Autodesk Fusion 360 part; units mm, degrees
(part 5 of 11)
  spline S55 degree 5 poles (35.2404, 10.7239) (35.2549, 10.7283) (35.284, 10.7368) (35.3279, 10.7484) (35.3869, 10.7619) (35.4614, 10.7761) (35.5364, 10.7882) (35.6117, 10.7992) (35.6872, 10.8094) (35.7628, 10.8192) (35.8385, 10.8286) (35.9144, 10.8373) (35.9904, 10.8452) (36.0666, 10.8522) (36.1431, 10.8581) (36.2198, 10.8632) (36.2966, 10.8675) (36.3735, 10.8712) (36.4506, 10.8743) (36.5277, 10.8769) (36.605, 10.879) (36.6823, 10.8805) (36.7598, 10.8814) (36.8374, 10.8817) (36.9151, 10.8814) (36.9928, 10.8806) (37.0707, 10.8792) (37.1487, 10.8772) (37.2267, 10.8748) (37.3048, 10.8719) (37.383, 10.8685) (37.4612, 10.8646) (37.5396, 10.8603) (37.618, 10.8554) (37.6964, 10.8501) (37.7749, 10.8443) (37.8535, 10.838) (37.9322, 10.8313) (38.0109, 10.8242) (38.0896, 10.8166) (38.1684, 10.8086) (38.2473, 10.8001) (38.3262, 10.7912) (38.4051, 10.7819) (38.4841, 10.7721) (38.5631, 10.762) (38.6422, 10.7514) (38.7213, 10.7404) (38.8005, 10.729) (38.8796, 10.7172) (38.9589, 10.705) (39.0381, 10.6924) (39.1174, 10.6794) (39.1967, 10.666) (39.276, 10.6523) (39.3554, 10.6381) (39.4347, 10.6236) (39.5142, 10.6087) (39.5936, 10.5934) (39.673, 10.5777) (39.7525, 10.5617) (39.832, 10.5453) (39.9115, 10.5285) (39.991, 10.5113) (40.0705, 10.4938) (40.1501, 10.4759) (40.2296, 10.4577) (40.3092, 10.4391) (40.3887, 10.4202) (40.4683, 10.4009) (40.5479, 10.3812) (40.6116, 10.3652) (40.6593, 10.3531) (40.6912, 10.3449) (40.7071, 10.3408) knots 0 0 0 0 0 0 0.01428571 0.02857143 0.04285714 0.05714286 0.07142857 0.08571429 0.1 0.11428571 0.12857143 0.14285714 0.15714286 0.17142857 0.18571429 0.2 0.21428571 0.22857143 0.24285714 0.25714286 0.27142857 0.28571429 0.3 0.31428571 0.32857143 0.34285714 0.35714286 0.37142857 0.38571429 0.4 0.41428571 0.42857143 0.44285714 0.45714286 0.47142857 0.48571429 0.5 0.51428571 0.52857143 0.54285714 0.55714286 0.57142857 0.58571429 0.6 0.61428571 0.62857143 0.64285714 0.65714286 0.67142857 0.68571429 0.7 0.71428571 0.72857143 0.74285714 0.75714286 0.77142857 0.78571429 0.8 0.81428571 0.82857143 0.84285714 0.85714286 0.87142857 0.88571429 0.9 0.91428571 0.92857143 0.94285714 0.95714286 0.97142857 0.98571429 1 1 1 1 1 1
  line L55 (35.2404, 10.7239) -> (35.182, 10.7062)
  arc A110 (33.9431, 11.346) -> (35.182, 10.7062) centre (34.8915, 11.6631) ccw
  arc A111 (33.9431, 11.346) -> (33.6119, 12.2925) centre (0, 0) ccw
  line L56 (8, -8) -> (-8, -8)
  line L57 (-8, -8) -> (-8, 8)
  line L58 (-8, 8) -> (8, 8)
  line L59 (8, 8) -> (8, -8)
  dimension "d23" = 8
  dimension "d24" = 8
  dimension "d25" = 16
  dimension "d26" = 16
  constraint horizontal L56
  constraint vertical L57
  constraint horizontal L58
  constraint vertical L59
  measures "d23" distance of L56 A1.centre
  measures "d24" distance of L57 A1.centre
  measures "d25" distance of L57.end L58.end
  measures "d26" distance of L56.start L58.end
extrude "Extrude4" cut sketch "Sketch3 (3)" against normal blind 6 contours L56 L57 L58 L59 sketch seen with x (1, 0, 0) y (0, 1, 0) z (0, 0, 1) at (0, 0, 12) bodies 2 in component "Spur Gear (28 teeth)"
component "Spur Gear (10 teeth)" placed x (1, 0, 0) y (0, 1, 0) z (0, 0, 1) at (0, 0, 0)
component "Spur Gear (28 teeth)" placed x (1, 0, 0) y (0, 1, 0) z (0, 0, 1) at (0, 0, -12)

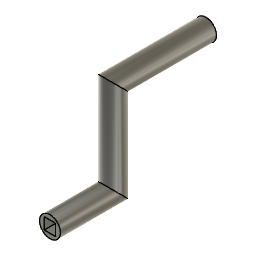
design "CRANK"
Autodesk Fusion 360 part; units mm, degrees
sketch "Sketch1" plane through (0, 0, 0) normal (0, 1, 0) x (1, 0, 0)
  circle A0 centre (0, 0) radius 31.369
  circle A1 centre (0, 0) radius 97.282
  dimension "d1" = 62.738
  dimension "d2" = 194.564
  constraint coincident A0.centre A1.centre
  measures "d1" diameter of A0
  measures "d2" diameter of A1
ref_plane "WorkPlane1" through (0, 2.921, 0) normal (0, 1, 0) x (1, 0, 0)
sketch "Sketch2" plane through (0, 2.921, 0) normal (0, 1, 0) x (1, 0, 0)
  circle A0 centre (0, 0) radius 31.369
  dimension "d15" = 62.738
  constraint coincident A0.centre origin
  measures "d15" diameter of A0
ref_plane "WorkPlane2" through (0, 59.563, 0) normal (0, 1, 0) x (1, 0, 0)
sketch "Sketch3" plane through (0, 59.563, 0) normal (0, 1, 0) x (1, 0, 0)
  circle A0 centre (0, 0) radius 31.369
  circle A1 centre (0, 0) radius 97.282
  dimension "d19" = 62.738
  dimension "d20" = 194.564
  constraint coincident A0.centre A1.centre
  measures "d19" diameter of A0
  measures "d20" diameter of A1
ref_plane "WorkPlane3" through (0, 2.921, 0) normal (0, 1, 0) x (1, 0, 0)
sketch "Sketch4" plane through (0, 2.921, 0) normal (0, 1, 0) x (1, 0, 0)
  circle A0 centre (0, 0) radius 92.456
  circle A1 centre (0, 0) radius 31.369
  dimension "d24" = 184.912
  dimension "d25" = 62.738
  constraint coincident A0.centre A1.centre
  measures "d24" diameter of A0
  measures "d25" diameter of A1
sketch "Sketch5" plane through (0, 0, 0) normal (0, 1, 0) x (1, 0, 0)
  circle A0 centre (0, 0) radius 30.861
  dimension "d28" = 61.722
  constraint coincident A0.centre origin
  measures "d28" diameter of A0
ref_plane "WorkPlane4" through (0, 76.2, 0) normal (0, 1, 0) x (1, 0, 0)
sketch "Sketch6" plane through (0, 76.2, 0) normal (0, 1, 0) x (1, 0, 0)
ref_plane "WorkPlane5" through (0, -19.05, 0) normal (0, -1, 0) x (-1, 0, 0)
sketch "Sketch7" plane through (0, -19.05, 0) normal (0, -1, 0) x (-1, 0, 0)
  circle A0 centre (0, 0) radius 25.4
  dimension "d33" = 50.8
  constraint coincident A0.centre origin
  measures "d33" diameter of A0
ref_plane "WorkPlane6" through (0, 62.23, 0) normal (0, 1, 0) x (1, 0, 0)
sketch "Sketch8" plane through (0, 62.23, 0) normal (0, 1, 0) x (1, 0, 0)
  circle A0 centre (0, 0) radius 31.425
  circle A1 centre (0, 0) radius 25.4019
  dimension "d38" = 62.85
  constraint coincident A0.centre A1.centre
  measures "d38" diameter of A0
ref_plane "WorkPlane7" through (0, 57.15, 0) normal (0, 1, 0) x (1, 0, 0)
sketch "Sketch9" plane through (0, 57.15, 0) normal (0, 1, 0) x (1, 0, 0)
  circle A0 centre (0, 0) radius 7.62
  dimension "d46" = 15.24
  constraint coincident A0.centre origin
  measures "d46" diameter of A0
ref_plane "WorkPlane8" through (0, 62.23, 0) normal (0, 1, 0) x (1, 0, 0)
sketch "Sketch10" plane through (0, 62.23, 0) normal (0, 1, 0) x (1, 0, 0)
  circle A0 centre (0, 0) radius 25.4
  circle A1 centre (0, 0) radius 44.45
  dimension "d50" = 50.8
  dimension "d51" = 88.9
  constraint coincident A0.centre A1.centre
  constraint concentric A0 A1
  measures "d50" diameter of A0
  measures "d51" diameter of A1
ref_plane "WorkPlane10" through (0, -19.05, 0) normal (0, -1, 0) x (-1, 0, 0)
sketch "Sketch12" plane through (0, -19.05, 0) normal (0, -1, 0) x (-1, 0, 0)
ref_plane "WorkPlane11" through (0, 86.36, 0) normal (0, 1, 0) x (1, 0, 0)
sketch "Sketch15" plane through (0, 86.36, 0) normal (0, 1, 0) x (1, 0, 0)
  line L0 (0, 0) -> (7.62, 0)
  line L1 (0, 0) -> (-7.62, 0)
  arc A0 (-7.62, 0) -> (7.62, 0) centre (0, 0) ccw
  dimension "d76" = 15.24
  constraint coincident L0.start L1.start
  constraint horizontal L0
  constraint parallel L0 L1
  measures "d76" diameter of A0
sketch "Sketch17" plane through (0, 86.36, 0) normal (0, 1, 0) x (1, 0, 0)
  circle A0 centre (0, 0) radius 9
  line L0 (7.8616, -0.2306) -> (-7.8616, -0.2306)
  arc A1 (7.8616, -0.2306) -> (-7.8616, -0.2306) centre (0, 0) ccw
  dimension "d80" = 18
  dimension "d81" = 15.73
  constraint coincident A0.centre A1.centre
  measures "d80" diameter of A0
  measures "d81" diameter of A1
ref_plane "WorkPlane12" through (0, 127.18, 0) normal (0, 1, 0) x (1, 0, 0)
sketch "Sketch18" plane through (0, 127.18, 0) normal (0, 1, 0) x (1, 0, 0)
  circle A0 centre (0, 0) radius 9
  dimension "d85" = 18
  constraint coincident A0.centre origin
  measures "d85" diameter of A0
ref_plane "WorkPlane14" through (9, 117.0493, 0) normal (1, 0, 0) x (0, 0, 1)
ref_plane "WorkPlane15" through (0, 117.0493, 0) normal (1, 0, 0) x (0, 0, 1)
sketch "Sketch19" plane through (0, 0, 0) normal (1, 0, 0) x (0, 1, 0)
  line L0 (127, 0) -> (141, 0)
  line L1 (141, 0) -> (141, 80)
  line L2 (141, 80) -> (221, 80)
  dimension "d89" = 80
  dimension "d90" = 80
  constraint horizontal L0
  constraint perpendicular L0 L1
  constraint perpendicular L1 L2
  measures "d89" distance of L0.end L1.end
  measures "d90" distance of L1.end L2.end
sweep "Sweep1" add profiles "Sketch18" path "Sketch19" along L0 L1 L2 section 1
ref_plane "WorkPlane16" through (0, -19.05, 0) normal (0, -1, 0) x (-1, 0, 0)
sketch "Sketch20" plane through (0, -19.05, 0) normal (0, -1, 0) x (-1, 0, 0)
  circle A0 centre (0, 0) radius 30
  dimension "d98" = 60
  constraint coincident A0.centre origin
  measures "d98" diameter of A0
ref_plane "WorkPlane17" through (0, -31.05, 0) normal (0, -1, 0) x (-1, 0, 0)
sketch "Sketch21" plane through (0, -31.05, 0) normal (0, -1, 0) x (-1, 0, 0)
ref_plane "WorkPlane18" through (0, 127, 0) normal (0, -1, 0) x (-1, 0, 0)
sketch "Sketch22" plane through (0, 127, 0) normal (0, -1, 0) x (-1, 0, 0)
  circle A0 centre (0, 0) radius 9
  line L0 (0, 0) -> (-7.6177, 0)
  line L1 (0, 0) -> (7.6177, 0)
  arc A1 (7.6177, 0) -> (-7.6177, 0) centre (0, 0) ccw
  dimension "d115" = 18
  constraint coincident A0.centre L0.start
  constraint concentric A0 A1
  constraint horizontal L0
  constraint parallel L0 L1
  measures "d115" diameter of A0
extrude "Extrude14" add sketch "Sketch22" along normal blind 40.5 contours A0 | L0 L1 A1
ref_plane "WorkPlane20" through (0, 86.5, 0) normal (0, -1, 0) x (-1, 0, 0)
sketch "Sketch24" plane through (0, 86.5, 0) normal (0, -1, 0) x (-1, 0, 0)
  line L0 (5, 5) -> (-5, 5)
  line L1 (-5, 5) -> (-5, -5)
  line L2 (-5, -5) -> (5, -5)
  line L3 (5, -5) -> (5, 5)
  line L4 (5, 5) -> (-5, -5) construction
  line L5 (-5, 5) -> (5, -5) construction
  dimension "d125" = 10
  dimension "d126" = 10
  constraint horizontal L0
  constraint perpendicular L0 L1
  constraint parallel L0 L2
  constraint parallel L1 L3
  constraint coincident L4 origin
  constraint coincident L5 origin
  measures "d125" distance of L1.end L2.end
  measures "d126" distance of L0.end L1.end
extrude "Extrude16" cut sketch "Sketch24" against normal blind 40

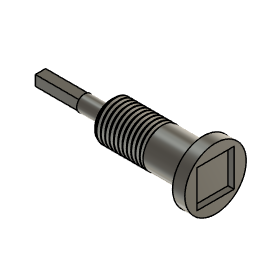
design "Green Part (Chamfered)"
Autodesk Fusion 360 part; units mm, degrees
sketch "Sketch1" plane through (0, 0, 0) normal (1, 0, 0) x (0, 1, 0)
  circle A0 centre (0, 0) radius 20
  dimension "d1" = 40
  constraint coincident A0.centre origin
  measures "d1" diameter of A0
extrude "Extrude1" add sketch "Sketch1" along normal blind 95
thread "Thread1" "ANSI Unified Screw Threads 1.5 1 1/2-6 UNC 3A" major diameter 37.8689 minor diameter 33.0606 pitch 4.2333 angle 60 modelled right hand crest width 0.6179 on face at (63.3333, 19.9751, -0.9969) from (0, 0, 0) to (55, 0, 0) crest through (-1.0583, 18.9344, 0)
sketch "Sketch2" plane through (0, 0, 0) normal (0, 1, 0) x (1, 0, 0)
  line L0 (0, 0) -> (0, -19)
  line L1 (0, -19) -> (8, -19)
  line L2 (8, -19) -> (5, -16)
  line L3 (5, -16) -> (5, 0)
  line L4 (5, 0) -> (0, 0)
  dimension "d6" = 19
  dimension "d7" = 5
  dimension "d8" = 45
  dimension "d9" = 3
  constraint coincident L0.start L4.end
  constraint vertical L0
  constraint perpendicular L0 L1
  constraint perpendicular L1 L3
  constraint perpendicular L0 L4
  measures "d6" distance of L0.start L0.end
  measures "d7" distance of L0 L3
  measures "d8" angle of L1 L2
  measures "d9" horizontal distance of L1.end L2.end
revolve "Revolve1" cut sketch "Sketch2" angle 360 about axis through (0, 0, 0) along (1, 0, 0)
sketch "Sketch3" plane through (5, 0, 0) normal (-1, 0, 0) x (0, -1, 0)
  circle A0 centre (0, 0) radius 16
  circle A1 centre (0, 0) radius 7.62
  dimension "d11" = 15.24
  constraint coincident A0.centre A1.centre
  measures "d11" diameter of A1
extrude "Extrude2" add sketch "Sketch3" along normal blind 26.2 contours A1
sketch "Sketch4" plane through (-21.2, 0, 0) normal (-1, 0, 0) x (0, -1, 0)
  circle A0 centre (0, 0) radius 7.62
  line L0 (5, -5) -> (-5, -5)
  line L1 (-5, -5) -> (-5, 5)
  line L2 (-5, 5) -> (5, 5)
  line L3 (5, 5) -> (5, -5)
  line L4 (5, -5) -> (-5, 5) construction
  line L5 (-5, -5) -> (5, 5) construction
  dimension "d14" = 10
  dimension "d15" = 10
  constraint horizontal L0
  constraint perpendicular L0 L1
  constraint parallel L0 L2
  constraint parallel L1 L3
  constraint coincident L4 A0.centre
  constraint coincident L5 A0.centre
  constraint coincident A0.centre origin
  measures "d14" distance of L1.end L2.end
  measures "d15" distance of L0.end L1.end
extrude "Extrude3" add sketch "Sketch4" along normal blind 43 contours L0 L1 L2 L3
sketch "Sketch5" plane through (95, 0, 0) normal (1, 0, 0) x (0, 1, 0)
  circle A0 centre (0, 0) radius 18.9344
  circle A1 centre (0, 0) radius 30
  dimension "d18" = 60
  constraint concentric A0 A1
  measures "d18" diameter of A1
extrude "Extrude4" add sketch "Sketch5" along normal blind 12 contours A0 | A1
sketch "Sketch6" plane through (107, 0, 0) normal (1, 0, 0) x (0, 1, 0)
  circle A0 centre (0, 0) radius 30
  line L0 (18.2, -18.2) -> (-18.2, -18.2)
  line L1 (-18.2, -18.2) -> (-18.2, 18.2)
  line L2 (-18.2, 18.2) -> (18.2, 18.2)
  line L3 (18.2, 18.2) -> (18.2, -18.2)
  line L4 (18.2, -18.2) -> (-18.2, 18.2) construction
  line L5 (-18.2, -18.2) -> (18.2, 18.2) construction
  dimension "d21" = 36.4
  dimension "d22" = 36.4
  constraint horizontal L0
  constraint perpendicular L0 L1
  constraint parallel L0 L2
  constraint parallel L1 L3
  constraint coincident L4 A0.centre
  constraint coincident L5 A0.centre
  constraint coincident A0.centre origin
  measures "d21" distance of L1.end L2.end
  measures "d22" distance of L0.start L2.end
extrude "Extrude5" cut sketch "Sketch6" against normal blind 6 contours L0 L1 L2 L3

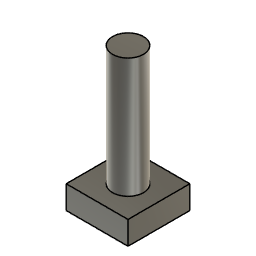
design "Blue Shaft"
Autodesk Fusion 360 part; units mm, degrees
sketch "Sketch1" plane through (0, 0, 0) normal (0, 0, 1) x (1, 0, 0)
  line L0 (-25, 25) -> (-9, 25)
  line L1 (-9, 25) -> (-9, 9)
  line L2 (-9, 9) -> (-25, 9)
  line L3 (-25, 9) -> (-25, 25)
  dimension "d1" = 16
  dimension "d2" = 16
  constraint horizontal L0
  constraint vertical L1
  constraint horizontal L2
  constraint vertical L3
  measures "d1" distance of L0.start L0.end
  measures "d2" distance of L0.end L1.end
extrude "Extrude1" add sketch "Sketch1" along normal blind 6
move_body "Move1" bodies 1 to x (1, 0, 0) y (0, 1, 0) z (0, 0, 1) at (18.0169, -15.1205, 0)
move_body "Move2" bodies 1 to x (1, 0, 0) y (0, 1, 0) z (0, 0, 1) at (-5.5215, -1.8795, -5.7458)
move_body "Move3" bodies 1 to x (1, 0, 0) y (0, 1, 0) z (0, 0, 1) at (-0.1134, -7.519, 0)
move_body "Move4" bodies 1 to x (1, 0, 0) y (0, 1, 0) z (0, 0, 1) at (4.618, 7.519, -0.2542)
sketch "Sketch2" plane through (0, 0, 0) normal (0, 0, 1) x (-1, 0, 0)
  line L0 (8, 8) -> (-8, 8)
  line L1 (-8, 8) -> (-8, -8)
  line L2 (-8, -8) -> (8, -8)
  line L3 (8, -8) -> (8, 8)
  circle A0 centre (0, 0) radius 4
  dimension "d5" = 8
  constraint coincident A0.centre origin
  measures "d5" diameter of A0
extrude "Extrude2" add sketch "Sketch2" along normal blind 31 contours A0

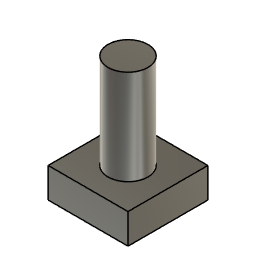
design "Black Shaft"
Autodesk Fusion 360 part; units mm, degrees
sketch "Sketch1" plane through (0, 0, 0) normal (0, 0, 1) x (1, 0, 0)
  line L0 (-8, 8) -> (8, 8)
  line L1 (8, 8) -> (8, -8)
  line L2 (8, -8) -> (-8, -8)
  line L3 (-8, -8) -> (-8, 8)
  dimension "d1" = 8
  dimension "d2" = 8
  dimension "d3" = 16
  dimension "d4" = 16
  constraint horizontal L0
  constraint vertical L1
  constraint horizontal L2
  constraint vertical L3
  measures "d1" distance of origin L1
  measures "d2" distance of origin L0
  measures "d3" distance of L1.end L2.end
  measures "d4" distance of L0.start L2.end
extrude "Extrude1" add sketch "Sketch1" along normal blind 6
sketch "Sketch2" plane through (0, 0, 6) normal (0, 0, 1) x (-1, 0, 0)
  line L0 (8, 8) -> (-8, 8)
  line L1 (-8, 8) -> (-8, -8)
  line L2 (-8, -8) -> (8, -8)
  line L3 (8, -8) -> (8, 8)
  circle A0 centre (0, 0) radius 4
  dimension "d7" = 8
  constraint coincident A0.centre origin
  measures "d7" diameter of A0
extrude "Extrude2" add sketch "Sketch2" along normal blind 19 contours A0

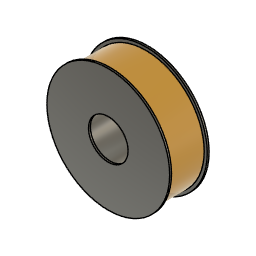
design "Spool"
Autodesk Fusion 360 part; units mm, degrees
sketch "Sketch1" plane through (0, 0, 0) normal (0, 1, 0) x (1, 0, 0)
  circle A0 centre (0, 0) radius 31.369
  circle A1 centre (0, 0) radius 97.282
  dimension "d1" = 62.738
  dimension "d2" = 194.564
  constraint coincident A0.centre A1.centre
  measures "d1" diameter of A0
  measures "d2" diameter of A1
extrude "Extrude1" add sketch "Sketch1" along normal blind 2.921 makes body 1
ref_plane "WorkPlane1" through (0, 2.921, 0) normal (0, 1, 0) x (1, 0, 0)
sketch "Sketch2" plane through (0, 2.921, 0) normal (0, 1, 0) x (1, 0, 0)
  circle A0 centre (0, 0) radius 31.369
  dimension "d15" = 62.738
  constraint coincident A0.centre origin
  measures "d15" diameter of A0
ref_plane "WorkPlane2" through (0, 59.563, 0) normal (0, 1, 0) x (1, 0, 0)
sketch "Sketch3" plane through (0, 59.563, 0) normal (0, 1, 0) x (1, 0, 0)
  circle A0 centre (0, 0) radius 31.369
  circle A1 centre (0, 0) radius 97.282
  dimension "d19" = 62.738
  dimension "d20" = 194.564
  constraint coincident A0.centre A1.centre
  measures "d19" diameter of A0
  measures "d20" diameter of A1
extrude "Extrude3" add sketch "Sketch3" along normal blind 2.921 separate body makes body 2
ref_plane "WorkPlane3" through (0, 2.921, 0) normal (0, 1, 0) x (1, 0, 0)
sketch "Sketch4" plane through (0, 2.921, 0) normal (0, 1, 0) x (1, 0, 0)
  circle A0 centre (0, 0) radius 92.456
  circle A1 centre (0, 0) radius 31.369
  dimension "d24" = 184.912
  dimension "d25" = 62.738
  constraint coincident A0.centre A1.centre
  measures "d24" diameter of A0
  measures "d25" diameter of A1
extrude "Extrude4" add sketch "Sketch4" along normal blind 56.642 separate body makes body 3
sketch "Sketch5" plane through (0, 0, 0) normal (0, 1, 0) x (1, 0, 0)
  circle A0 centre (0, 0) radius 30.861
  dimension "d28" = 61.722
  constraint coincident A0.centre origin
  measures "d28" diameter of A0
ref_plane "WorkPlane4" through (0, 76.2, 0) normal (0, 1, 0) x (1, 0, 0)
sketch "Sketch6" plane through (0, 76.2, 0) normal (0, 1, 0) x (1, 0, 0)
ref_plane "WorkPlane5" through (0, -19.05, 0) normal (0, -1, 0) x (-1, 0, 0)
sketch "Sketch7" plane through (0, -19.05, 0) normal (0, -1, 0) x (-1, 0, 0)
  circle A0 centre (0, 0) radius 25.4
  dimension "d33" = 50.8
  constraint coincident A0.centre origin
  measures "d33" diameter of A0
ref_plane "WorkPlane6" through (0, 62.23, 0) normal (0, 1, 0) x (1, 0, 0)
sketch "Sketch8" plane through (0, 62.23, 0) normal (0, 1, 0) x (1, 0, 0)
  circle A0 centre (0, 0) radius 31.425
  circle A1 centre (0, 0) radius 25.4019
  dimension "d38" = 62.85
  constraint coincident A0.centre A1.centre
  measures "d38" diameter of A0
ref_plane "WorkPlane7" through (0, 57.15, 0) normal (0, 1, 0) x (1, 0, 0)
sketch "Sketch9" plane through (0, 57.15, 0) normal (0, 1, 0) x (1, 0, 0)
  circle A0 centre (0, 0) radius 7.62
  dimension "d46" = 15.24
  constraint coincident A0.centre origin
  measures "d46" diameter of A0
ref_plane "WorkPlane8" through (0, 62.23, 0) normal (0, 1, 0) x (1, 0, 0)
sketch "Sketch10" plane through (0, 62.23, 0) normal (0, 1, 0) x (1, 0, 0)
  circle A0 centre (0, 0) radius 25.4
  circle A1 centre (0, 0) radius 44.45
  dimension "d50" = 50.8
  dimension "d51" = 88.9
  constraint coincident A0.centre A1.centre
  constraint concentric A0 A1
  measures "d50" diameter of A0
  measures "d51" diameter of A1
ref_plane "WorkPlane10" through (0, -19.05, 0) normal (0, -1, 0) x (-1, 0, 0)
sketch "Sketch12" plane through (0, -19.05, 0) normal (0, -1, 0) x (-1, 0, 0)
ref_plane "WorkPlane11" through (0, 86.36, 0) normal (0, 1, 0) x (1, 0, 0)
sketch "Sketch15" plane through (0, 86.36, 0) normal (0, 1, 0) x (1, 0, 0)
  line L0 (0, 0) -> (7.62, 0)
  line L1 (0, 0) -> (-7.62, 0)
  arc A0 (-7.62, 0) -> (7.62, 0) centre (0, 0) ccw
  dimension "d76" = 15.24
  constraint coincident L0.start L1.start
  constraint horizontal L0
  constraint parallel L0 L1
  measures "d76" diameter of A0
sketch "Sketch17" plane through (0, 86.36, 0) normal (0, 1, 0) x (1, 0, 0)
  circle A0 centre (0, 0) radius 9
  line L0 (7.8616, -0.2306) -> (-7.8616, -0.2306)
  arc A1 (7.8616, -0.2306) -> (-7.8616, -0.2306) centre (0, 0) ccw
  dimension "d80" = 18
  dimension "d81" = 15.73
  constraint coincident A0.centre A1.centre
  measures "d80" diameter of A0
  measures "d81" diameter of A1
ref_plane "WorkPlane12" through (0, 127.18, 0) normal (0, 1, 0) x (1, 0, 0)
sketch "Sketch18" plane through (0, 127.18, 0) normal (0, 1, 0) x (1, 0, 0)
  circle A0 centre (0, 0) radius 9
  dimension "d85" = 18
  constraint coincident A0.centre origin
  measures "d85" diameter of A0
ref_plane "WorkPlane14" through (9, 117.0493, 0) normal (1, 0, 0) x (0, 0, 1)
ref_plane "WorkPlane15" through (0, 117.0493, 0) normal (1, 0, 0) x (0, 0, 1)
sketch "Sketch19" plane through (0, 0, 0) normal (1, 0, 0) x (0, 1, 0)
  line L0 (127, 0) -> (141, 0)
  line L1 (141, 0) -> (141, 80)
  line L2 (141, 80) -> (221, 80)
  dimension "d89" = 80
  dimension "d90" = 80
  constraint horizontal L0
  constraint perpendicular L0 L1
  constraint perpendicular L1 L2
  measures "d89" distance of L0.end L1.end
  measures "d90" distance of L1.end L2.end
ref_plane "WorkPlane16" through (0, -19.05, 0) normal (0, -1, 0) x (-1, 0, 0)
sketch "Sketch20" plane through (0, -19.05, 0) normal (0, -1, 0) x (-1, 0, 0)
  circle A0 centre (0, 0) radius 30
  dimension "d98" = 60
  constraint coincident A0.centre origin
  measures "d98" diameter of A0
ref_plane "WorkPlane17" through (0, -31.05, 0) normal (0, -1, 0) x (-1, 0, 0)
sketch "Sketch21" plane through (0, -31.05, 0) normal (0, -1, 0) x (-1, 0, 0)
ref_plane "WorkPlane18" through (0, 127, 0) normal (0, -1, 0) x (-1, 0, 0)
sketch "Sketch22" plane through (0, 127, 0) normal (0, -1, 0) x (-1, 0, 0)
  circle A0 centre (0, 0) radius 9
  line L0 (0, 0) -> (-7.6177, 0)
  line L1 (0, 0) -> (7.6177, 0)
  arc A1 (7.6177, 0) -> (-7.6177, 0) centre (0, 0) ccw
  dimension "d115" = 18
  constraint coincident A0.centre L0.start
  constraint concentric A0 A1
  constraint horizontal L0
  constraint parallel L0 L1
  measures "d115" diameter of A0

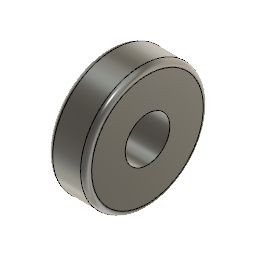
design "608RS Bearing"
Autodesk Fusion 360 part; units mm, degrees
sketch "Sketch1" plane through (0, 0, 0) normal (1, 0, 0) x (0, 1, 0)
  circle A0 centre (0, 0) radius 11
  circle A1 centre (0, 0) radius 4
  dimension "d1" = 22
  dimension "d2" = 8
  constraint coincident A0.centre A1.centre
  constraint concentric A0 A1
  measures "d1" diameter of A0
  measures "d2" diameter of A1
extrude "Extrude1" add sketch "Sketch1" along normal blind 7
fillet "Fillet1" radius 1 2 edges at (0, -10.2556, -3.9778) (7, -10.2556, -3.9778)

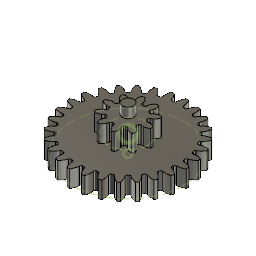
design "Blue Gear (new)"
description: Spur Gear; Module: 2.800000; Num Teeth: 28; Pressure Angle: 20.000000; Backlash: 0.00 mm
description: Spur Gear; Module: 2.800000; Num Teeth: 10; Pressure Angle: 20.000000; Backlash: 0.00 mm
Autodesk Fusion 360 part; units mm, degrees
sketch "Sketch1" plane through (0, 0, 0) normal (0, 0, 1) x (1, 0, 0) in component "Spur Gear (28 teeth)"
  circle A0 centre (0, 0) radius 35.7892
extrude "Extrude1" add sketch "Sketch1" along normal blind 12 makes body 1 in component "Spur Gear (28 teeth)"
sketch "Sketch2" plane through (0, 0, 0) normal (0, 0, 1) x (1, 0, 0) in component "Spur Gear (28 teeth)"
  spline S0 degree 5 poles (36.7431, -2.6133) (36.7583, -2.6144) (36.7885, -2.6161) (36.8339, -2.6177) (36.8945, -2.6178) (36.9702, -2.615) (37.0461, -2.6101) (37.1219, -2.6041) (37.1978, -2.5973) (37.2736, -2.59) (37.3495, -2.5823) (37.4254, -2.5739) (37.5013, -2.5647) (37.5772, -2.5545) (37.6531, -2.5433) (37.7289, -2.5312) (37.8048, -2.5183) (37.8806, -2.5048) (37.9564, -2.4907) (38.0322, -2.476) (38.108, -2.4608) (38.1838, -2.4451) (38.2595, -2.4287) (38.3352, -2.4118) (38.4109, -2.3942) (38.4865, -2.3761) (38.5621, -2.3574) (38.6377, -2.3382) (38.7132, -2.3184) (38.7887, -2.2982) (38.8642, -2.2775) (38.9396, -2.2563) (39.015, -2.2346) (39.0904, -2.2125) (39.1657, -2.1898) (39.2409, -2.1667) (39.3162, -2.1431) (39.3913, -2.1191) (39.4665, -2.0946) (39.5415, -2.0697) (39.6166, -2.0443) (39.6916, -2.0185) (39.7665, -1.9923) (39.8414, -1.9656) (39.9162, -1.9385) (39.991, -1.911) (40.0658, -1.8831) (40.1405, -1.8548) (40.2151, -1.8261) (40.2896, -1.797) (40.3642, -1.7675) (40.4386, -1.7375) (40.513, -1.7072) (40.5874, -1.6765) (40.6616, -1.6455) (40.7359, -1.614) (40.81, -1.5822) (40.8841, -1.55) (40.9581, -1.5174) (41.0321, -1.4844) (41.106, -1.4511) (41.1798, -1.4174) (41.2536, -1.3834) (41.3273, -1.349) (41.401, -1.3142) (41.4745, -1.2791) (41.548, -1.2436) (41.6215, -1.2078) (41.6948, -1.1716) (41.7681, -1.1351) (41.8413, -1.0982) (41.8998, -1.0684) (41.9437, -1.0459) (41.9729, -1.0309) (41.9875, -1.0233) knots 0 0 0 0 0 0 0.01428571 0.02857143 0.04285714 0.05714286 0.07142857 0.08571429 0.1 0.11428571 0.12857143 0.14285714 0.15714286 0.17142857 0.18571429 0.2 0.21428571 0.22857143 0.24285714 0.25714286 0.27142857 0.28571429 0.3 0.31428571 0.32857143 0.34285714 0.35714286 0.37142857 0.38571429 0.4 0.41428571 0.42857143 0.44285714 0.45714286 0.47142857 0.48571429 0.5 0.51428571 0.52857143 0.54285714 0.55714286 0.57142857 0.58571429 0.6 0.61428571 0.62857143 0.64285714 0.65714286 0.67142857 0.68571429 0.7 0.71428571 0.72857143 0.74285714 0.75714286 0.77142857 0.78571429 0.8 0.81428571 0.82857143 0.84285714 0.85714286 0.87142857 0.88571429 0.9 0.91428571 0.92857143 0.94285714 0.95714286 0.97142857 0.98571429 1 1 1 1 1 1
  spline S1 degree 5 poles (36.7431, 2.6133) (36.7583, 2.6144) (36.7885, 2.6161) (36.8339, 2.6177) (36.8945, 2.6178) (36.9702, 2.615) (37.0461, 2.6101) (37.1219, 2.6041) (37.1978, 2.5973) (37.2736, 2.59) (37.3495, 2.5823) (37.4254, 2.5739) (37.5013, 2.5647) (37.5772, 2.5545) (37.6531, 2.5433) (37.7289, 2.5312) (37.8048, 2.5183) (37.8806, 2.5048) (37.9564, 2.4907) (38.0322, 2.476) (38.108, 2.4608) (38.1838, 2.4451) (38.2595, 2.4287) (38.3352, 2.4118) (38.4109, 2.3942) (38.4865, 2.3761) (38.5621, 2.3574) (38.6377, 2.3382) (38.7132, 2.3184) (38.7887, 2.2982) (38.8642, 2.2775) (38.9396, 2.2563) (39.015, 2.2346) (39.0904, 2.2125) (39.1657, 2.1898) (39.2409, 2.1667) (39.3162, 2.1431) (39.3913, 2.1191) (39.4665, 2.0946) (39.5415, 2.0697) (39.6166, 2.0443) (39.6916, 2.0185) (39.7665, 1.9923) (39.8414, 1.9656) (39.9162, 1.9385) (39.991, 1.911) (40.0658, 1.8831) (40.1405, 1.8548) (40.2151, 1.8261) (40.2896, 1.797) (40.3642, 1.7675) (40.4386, 1.7375) (40.513, 1.7072) (40.5874, 1.6765) (40.6616, 1.6455) (40.7359, 1.614) (40.81, 1.5822) (40.8841, 1.55) (40.9581, 1.5174) (41.0321, 1.4844) (41.106, 1.4511) (41.1798, 1.4174) (41.2536, 1.3834) (41.3273, 1.349) (41.401, 1.3142) (41.4745, 1.2791) (41.548, 1.2436) (41.6215, 1.2078) (41.6948, 1.1716) (41.7681, 1.1351) (41.8413, 1.0982) (41.8998, 1.0684) (41.9437, 1.0459) (41.9729, 1.0309) (41.9875, 1.0233) knots 0 0 0 0 0 0 0.01428571 0.02857143 0.04285714 0.05714286 0.07142857 0.08571429 0.1 0.11428571 0.12857143 0.14285714 0.15714286 0.17142857 0.18571429 0.2 0.21428571 0.22857143 0.24285714 0.25714286 0.27142857 0.28571429 0.3 0.31428571 0.32857143 0.34285714 0.35714286 0.37142857 0.38571429 0.4 0.41428571 0.42857143 0.44285714 0.45714286 0.47142857 0.48571429 0.5 0.51428571 0.52857143 0.54285714 0.55714286 0.57142857 0.58571429 0.6 0.61428571 0.62857143 0.64285714 0.65714286 0.67142857 0.68571429 0.7 0.71428571 0.72857143 0.74285714 0.75714286 0.77142857 0.78571429 0.8 0.81428571 0.82857143 0.84285714 0.85714286 0.87142857 0.88571429 0.9 0.91428571 0.92857143 0.94285714 0.95714286 0.97142857 0.98571429 1 1 1 1 1 1
  arc A0 (41.9875, -1.0233) -> (41.9875, 1.0233) centre (0, 0) ccw
  line L0 (35.689, -2.5391) -> (36.7431, -2.6133)
  line L1 (35.689, 2.5391) -> (36.7431, 2.6133)
  line L2 (35.689, -2.5391) -> (35.689, 2.5391)
  point P0 (37.1135, -2.6046)
  point P1 (37.4859, -2.5664)
  point P2 (37.8595, -2.5085)
  point P3 (38.234, -2.4342)
  point P4 (38.6091, -2.3454)
  point P5 (38.9846, -2.2433)
  point P6 (39.3604, -2.1289)
  point P7 (39.7364, -2.0027)
  point P8 (40.1123, -1.8654)
  point P9 (40.4882, -1.7173)
  point P10 (40.8637, -1.5588)
  point P11 (41.2389, -1.3901)
  point P12 (41.6135, -1.2116)
  point P13 (37.1135, 2.6046)
  point P14 (37.4859, 2.5664)
  point P15 (37.8595, 2.5085)
  point P16 (38.234, 2.4342)
  point P17 (38.6091, 2.3454)
  point P18 (38.9846, 2.2433)
  point P19 (39.3604, 2.1289)
  point P20 (39.7364, 2.0027)
  point P21 (40.1123, 1.8654)
  point P22 (40.4882, 1.7173)
  point P23 (40.8637, 1.5588)
  point P24 (41.2389, 1.3901)
  point P25 (41.6135, 1.2116)
extrude "Extrude2" add sketch "Sketch2" along normal blind 12 bodies 1 in component "Spur Gear (28 teeth)"
fillet "Fillet1" radius 1 2 edges at (35.699, -2.5397, 6) (35.699, 2.5397, 6) on bodies 1 in component "Spur Gear (28 teeth)"
pattern_circular "C-Pattern1" count 28 over 360 about axis through (0, 0, 0) along (0, 0, 1) of "Extrude2", "Fillet1" in component "Spur Gear (28 teeth)"
sketch "Sketch3" plane through (0, 0, 0) normal (0, 0, 1) x (1, 0, 0) in component "Spur Gear (28 teeth)"
  circle A0 centre (0, 0) radius 39.2 construction
sketch "Sketch1 (2)" plane through (0, 0, 0) normal (0, 0, 1) x (1, 0, 0) in component "Spur Gear (10 teeth)"
  circle A0 centre (0, 0) radius 10.5892
extrude "Extrude1'" add sketch "Sketch1 (2)" along normal blind 12 separate body makes body 2 in component "Spur Gear (10 teeth)"
sketch "Sketch2 (2)" plane through (0, 0, 0) normal (0, 0, 1) x (1, 0, 0) in component "Spur Gear (10 teeth)"
  spline S0 degree 5 poles (12.9616, -2.2514) (12.9724, -2.2533) (12.9939, -2.2566) (13.0264, -2.2606) (13.0698, -2.2637) (13.1245, -2.2647) (13.1793, -2.2636) (13.2343, -2.2613) (13.2894, -2.2583) (13.3446, -2.2548) (13.3998, -2.2507) (13.4551, -2.246) (13.5104, -2.2404) (13.5658, -2.2337) (13.6212, -2.226) (13.6767, -2.2173) (13.7323, -2.2079) (13.7878, -2.1977) (13.8434, -2.187) (13.899, -2.1756) (13.9546, -2.1637) (14.0101, -2.1511) (14.0657, -2.138) (14.1213, -2.1241) (14.1769, -2.1096) (14.2325, -2.0944) (14.2881, -2.0787) (14.3436, -2.0624) (14.3991, -2.0455) (14.4546, -2.0281) (14.5101, -2.0101) (14.5655, -1.9917) (14.6209, -1.9726) (14.6763, -1.953) (14.7316, -1.9329) (14.7869, -1.9123) (14.8421, -1.8911) (14.8973, -1.8695) (14.9524, -1.8473) (15.0075, -1.8247) (15.0626, -1.8015) (15.1175, -1.7779) (15.1724, -1.7538) (15.2273, -1.7292) (15.282, -1.7041) (15.3368, -1.6785) (15.3914, -1.6525) (15.446, -1.626) (15.5004, -1.5991) (15.5548, -1.5717) (15.6092, -1.5439) (15.6634, -1.5156) (15.7176, -1.4868) (15.7717, -1.4576) (15.8256, -1.428) (15.8795, -1.3979) (15.9333, -1.3674) (15.9871, -1.3365) (16.0407, -1.3051) (16.0942, -1.2733) (16.1476, -1.2411) (16.2009, -1.2085) (16.2541, -1.1755) (16.3072, -1.142) (16.3602, -1.1081) (16.413, -1.0738) (16.4658, -1.0391) (16.5184, -1.004) (16.571, -0.9685) (16.6234, -0.9327) (16.6757, -0.8964) (16.7174, -0.867) (16.7486, -0.8448) (16.7695, -0.8299) (16.7799, -0.8225) knots 0 0 0 0 0 0 0.01428571 0.02857143 0.04285714 0.05714286 0.07142857 0.08571429 0.1 0.11428571 0.12857143 0.14285714 0.15714286 0.17142857 0.18571429 0.2 0.21428571 0.22857143 0.24285714 0.25714286 0.27142857 0.28571429 0.3 0.31428571 0.32857143 0.34285714 0.35714286 0.37142857 0.38571429 0.4 0.41428571 0.42857143 0.44285714 0.45714286 0.47142857 0.48571429 0.5 0.51428571 0.52857143 0.54285714 0.55714286 0.57142857 0.58571429 0.6 0.61428571 0.62857143 0.64285714 0.65714286 0.67142857 0.68571429 0.7 0.71428571 0.72857143 0.74285714 0.75714286 0.77142857 0.78571429 0.8 0.81428571 0.82857143 0.84285714 0.85714286 0.87142857 0.88571429 0.9 0.91428571 0.92857143 0.94285714 0.95714286 0.97142857 0.98571429 1 1 1 1 1 1
  spline S1 degree 5 poles (12.9616, 2.2514) (12.9724, 2.2533) (12.9939, 2.2566) (13.0264, 2.2606) (13.0698, 2.2637) (13.1245, 2.2647) (13.1793, 2.2636) (13.2343, 2.2613) (13.2894, 2.2583) (13.3446, 2.2548) (13.3998, 2.2507) (13.4551, 2.246) (13.5104, 2.2404) (13.5658, 2.2337) (13.6212, 2.226) (13.6767, 2.2173) (13.7323, 2.2079) (13.7878, 2.1977) (13.8434, 2.187) (13.899, 2.1756) (13.9546, 2.1637) (14.0101, 2.1511) (14.0657, 2.138) (14.1213, 2.1241) (14.1769, 2.1096) (14.2325, 2.0944) (14.2881, 2.0787) (14.3436, 2.0624) (14.3991, 2.0455) (14.4546, 2.0281) (14.5101, 2.0101) (14.5655, 1.9917) (14.6209, 1.9726) (14.6763, 1.953) (14.7316, 1.9329) (14.7869, 1.9123) (14.8421, 1.8911) (14.8973, 1.8695) (14.9524, 1.8473) (15.0075, 1.8247) (15.0626, 1.8015) (15.1175, 1.7779) (15.1724, 1.7538) (15.2273, 1.7292) (15.282, 1.7041) (15.3368, 1.6785) (15.3914, 1.6525) (15.446, 1.626) (15.5004, 1.5991) (15.5548, 1.5717) (15.6092, 1.5439) (15.6634, 1.5156) (15.7176, 1.4868) (15.7717, 1.4576) (15.8256, 1.428) (15.8795, 1.3979) (15.9333, 1.3674) (15.9871, 1.3365) (16.0407, 1.3051) (16.0942, 1.2733) (16.1476, 1.2411) (16.2009, 1.2085) (16.2541, 1.1755) (16.3072, 1.142) (16.3602, 1.1081) (16.413, 1.0738) (16.4658, 1.0391) (16.5184, 1.004) (16.571, 0.9685) (16.6234, 0.9327) (16.6757, 0.8964) (16.7174, 0.867) (16.7486, 0.8448) (16.7695, 0.8299) (16.7799, 0.8225) knots 0 0 0 0 0 0 0.01428571 0.02857143 0.04285714 0.05714286 0.07142857 0.08571429 0.1 0.11428571 0.12857143 0.14285714 0.15714286 0.17142857 0.18571429 0.2 0.21428571 0.22857143 0.24285714 0.25714286 0.27142857 0.28571429 0.3 0.31428571 0.32857143 0.34285714 0.35714286 0.37142857 0.38571429 0.4 0.41428571 0.42857143 0.44285714 0.45714286 0.47142857 0.48571429 0.5 0.51428571 0.52857143 0.54285714 0.55714286 0.57142857 0.58571429 0.6 0.61428571 0.62857143 0.64285714 0.65714286 0.67142857 0.68571429 0.7 0.71428571 0.72857143 0.74285714 0.75714286 0.77142857 0.78571429 0.8 0.81428571 0.82857143 0.84285714 0.85714286 0.87142857 0.88571429 0.9 0.91428571 0.92857143 0.94285714 0.95714286 0.97142857 0.98571429 1 1 1 1 1 1
  arc A0 (16.7799, -0.8225) -> (16.7799, 0.8225) centre (0, 0) ccw
  line L0 (10.4231, -1.8122) -> (12.9616, -2.2514)
  line L1 (10.4231, 1.8122) -> (12.9616, 2.2514)
  line L2 (10.4231, -1.8122) -> (10.4231, 1.8122)
  point P0 (13.224, -2.2616)
  point P1 (13.4913, -2.2422)
  point P2 (13.7615, -2.2025)
  point P3 (14.0339, -2.1454)
  point P4 (14.3079, -2.0728)
  point P5 (14.583, -1.9856)
  point P6 (14.8588, -1.8845)
  point P7 (15.135, -1.7701)
  point P8 (15.4111, -1.6429)
  point P9 (15.6869, -1.503)
  point P10 (15.962, -1.3508)
  point P11 (16.2361, -1.1866)
  point P12 (16.5088, -1.0104)
  point P13 (13.224, 2.2616)
  point P14 (13.4913, 2.2422)
  point P15 (13.7615, 2.2025)
  point P16 (14.0339, 2.1454)
  point P17 (14.3079, 2.0728)
  point P18 (14.583, 1.9856)
  point P19 (14.8588, 1.8845)
  point P20 (15.135, 1.7701)
  point P21 (15.4111, 1.6429)
  point P22 (15.6869, 1.503)
  point P23 (15.962, 1.3508)
  point P24 (16.2361, 1.1866)
  point P25 (16.5088, 1.0104)
extrude "Extrude2'" add sketch "Sketch2 (2)" along normal blind 12 bodies 2 in component "Spur Gear (10 teeth)"
fillet "Fillet1'" radius 1 2 edges at (10.4327, -1.8139, 6) (10.4327, 1.8139, 6) on bodies 2 in component "Spur Gear (10 teeth)"
pattern_circular "C-Pattern1'" count 10 over 360 about axis through (0, 0, 0) along (0, 0, 1) of "Extrude2'", "Fillet1'" in component "Spur Gear (10 teeth)"
sketch "Sketch3 (2)" plane through (0, 0, 0) normal (0, 0, 1) x (1, 0, 0) in component "Spur Gear (10 teeth)"
  circle A0 centre (0, 0) radius 14 construction